Autodesk Fusion 360 part; units mm, degrees
(part 3 of 5)
sketch "belly_pb10" plane through (120.4, 0, 0) normal (1, 0, 0) x (0, 0, -1)
  line L0 (20.5, -27) -> (22.2245, -23.1429)
  line L1 (22.2245, -23.1429) -> (23.6837, -19.2857)
  line L2 (23.6837, -19.2857) -> (24.8776, -15.4286)
  line L3 (24.8776, -15.4286) -> (25.8061, -11.5714)
  line L4 (25.8061, -11.5714) -> (26.4694, -7.7143)
  line L5 (26.4694, -7.7143) -> (26.8673, -3.8571)
  line L6 (26.8673, -3.8571) -> (27, 0)
  line L7 (27, 0) -> (26.8673, 3.8571)
  line L8 (26.8673, 3.8571) -> (26.4694, 7.7143)
  line L9 (26.4694, 7.7143) -> (25.8061, 11.5714)
  line L10 (25.8061, 11.5714) -> (24.8776, 15.4286)
  line L11 (24.8776, 15.4286) -> (23.6837, 19.2857)
  line L12 (23.6837, 19.2857) -> (22.2245, 23.1429)
  line L13 (22.2245, 23.1429) -> (20.5, 27)
  line L14 (20.5, 27) -> (18.5, 27)
  line L15 (18.5, 27) -> (20.2245, 23.1429)
  line L16 (20.2245, 23.1429) -> (21.6837, 19.2857)
  line L17 (21.6837, 19.2857) -> (22.8776, 15.4286)
  line L18 (22.8776, 15.4286) -> (23.8061, 11.5714)
  line L19 (23.8061, 11.5714) -> (24.4694, 7.7143)
  line L20 (24.4694, 7.7143) -> (24.8673, 3.8571)
  line L21 (24.8673, 3.8571) -> (25, 0)
  line L22 (25, 0) -> (24.8673, -3.8571)
  line L23 (24.8673, -3.8571) -> (24.4694, -7.7143)
  line L24 (24.4694, -7.7143) -> (23.8061, -11.5714)
  line L25 (23.8061, -11.5714) -> (22.8776, -15.4286)
  line L26 (22.8776, -15.4286) -> (21.6837, -19.2857)
  line L27 (21.6837, -19.2857) -> (20.2245, -23.1429)
  line L28 (20.2245, -23.1429) -> (18.5, -27)
  line L29 (18.5, -27) -> (20.5, -27)
loft "Loft29" add profiles "belly_pa10", "belly_pb10" section 1 section 2 separate body makes body 29
ref_plane "WorkPlane59" through (119.6, 0, 0) normal (1, 0, 0) x (0, 1, 0)
sketch "belly_pa11" plane through (119.6, 0, 0) normal (1, 0, 0) x (0, 0, -1)
  line L0 (20.5, -27) -> (22.2245, -23.1429)
  line L1 (22.2245, -23.1429) -> (23.6837, -19.2857)
  line L2 (23.6837, -19.2857) -> (24.8776, -15.4286)
  line L3 (24.8776, -15.4286) -> (25.8061, -11.5714)
  line L4 (25.8061, -11.5714) -> (26.4694, -7.7143)
  line L5 (26.4694, -7.7143) -> (26.8673, -3.8571)
  line L6 (26.8673, -3.8571) -> (27, 0)
  line L7 (27, 0) -> (26.8673, 3.8571)
  line L8 (26.8673, 3.8571) -> (26.4694, 7.7143)
  line L9 (26.4694, 7.7143) -> (25.8061, 11.5714)
  line L10 (25.8061, 11.5714) -> (24.8776, 15.4286)
  line L11 (24.8776, 15.4286) -> (23.6837, 19.2857)
  line L12 (23.6837, 19.2857) -> (22.2245, 23.1429)
  line L13 (22.2245, 23.1429) -> (20.5, 27)
  line L14 (20.5, 27) -> (18.5, 27)
  line L15 (18.5, 27) -> (20.2245, 23.1429)
  line L16 (20.2245, 23.1429) -> (21.6837, 19.2857)
  line L17 (21.6837, 19.2857) -> (22.8776, 15.4286)
  line L18 (22.8776, 15.4286) -> (23.8061, 11.5714)
  line L19 (23.8061, 11.5714) -> (24.4694, 7.7143)
  line L20 (24.4694, 7.7143) -> (24.8673, 3.8571)
  line L21 (24.8673, 3.8571) -> (25, 0)
  line L22 (25, 0) -> (24.8673, -3.8571)
  line L23 (24.8673, -3.8571) -> (24.4694, -7.7143)
  line L24 (24.4694, -7.7143) -> (23.8061, -11.5714)
  line L25 (23.8061, -11.5714) -> (22.8776, -15.4286)
  line L26 (22.8776, -15.4286) -> (21.6837, -19.2857)
  line L27 (21.6837, -19.2857) -> (20.2245, -23.1429)
  line L28 (20.2245, -23.1429) -> (18.5, -27)
  line L29 (18.5, -27) -> (20.5, -27)
ref_plane "WorkPlane60" through (124.6857, 0, 0) normal (1, 0, 0) x (0, 1, 0)
sketch "belly_pb11" plane through (124.6857, 0, 0) normal (1, 0, 0) x (0, 0, -1)
  line L0 (18.3003, -24.3221) -> (19.8472, -20.8475)
  line L1 (19.8472, -20.8475) -> (21.1561, -17.3729)
  line L2 (21.1561, -17.3729) -> (22.227, -13.8983)
  line L3 (22.227, -13.8983) -> (23.0599, -10.4238)
  line L4 (23.0599, -10.4238) -> (23.6549, -6.9492)
  line L5 (23.6549, -6.9492) -> (24.0118, -3.4746)
  line L6 (24.0118, -3.4746) -> (24.1308, 0)
  line L7 (24.1308, 0) -> (24.0118, 3.4746)
  line L8 (24.0118, 3.4746) -> (23.6549, 6.9492)
  line L9 (23.6549, 6.9492) -> (23.0599, 10.4238)
  line L10 (23.0599, 10.4238) -> (22.227, 13.8983)
  line L11 (22.227, 13.8983) -> (21.1561, 17.3729)
  line L12 (21.1561, 17.3729) -> (19.8472, 20.8475)
  line L13 (19.8472, 20.8475) -> (18.3003, 24.3221)
  line L14 (18.3003, 24.3221) -> (16.3003, 24.3221)
  line L15 (16.3003, 24.3221) -> (17.8472, 20.8475)
  line L16 (17.8472, 20.8475) -> (19.1561, 17.3729)
  line L17 (19.1561, 17.3729) -> (20.227, 13.8983)
  line L18 (20.227, 13.8983) -> (21.0599, 10.4238)
  line L19 (21.0599, 10.4238) -> (21.6549, 6.9492)
  line L20 (21.6549, 6.9492) -> (22.0118, 3.4746)
  line L21 (22.0118, 3.4746) -> (22.1308, 0)
  line L22 (22.1308, 0) -> (22.0118, -3.4746)
  line L23 (22.0118, -3.4746) -> (21.6549, -6.9492)
  line L24 (21.6549, -6.9492) -> (21.0599, -10.4238)
  line L25 (21.0599, -10.4238) -> (20.227, -13.8983)
  line L26 (20.227, -13.8983) -> (19.1561, -17.3729)
  line L27 (19.1561, -17.3729) -> (17.8472, -20.8475)
  line L28 (17.8472, -20.8475) -> (16.3003, -24.3221)
  line L29 (16.3003, -24.3221) -> (18.3003, -24.3221)
loft "Loft30" add profiles "belly_pa11", "belly_pb11" section 1 section 2 separate body makes body 30
ref_plane "WorkPlane61" through (123.8857, 0, 0) normal (1, 0, 0) x (0, 1, 0)
sketch "belly_pa12" plane through (123.8857, 0, 0) normal (1, 0, 0) x (0, 0, -1)
  line L0 (18.3003, -24.3221) -> (19.8472, -20.8475)
  line L1 (19.8472, -20.8475) -> (21.1561, -17.3729)
  line L2 (21.1561, -17.3729) -> (22.227, -13.8983)
  line L3 (22.227, -13.8983) -> (23.0599, -10.4238)
  line L4 (23.0599, -10.4238) -> (23.6549, -6.9492)
  line L5 (23.6549, -6.9492) -> (24.0118, -3.4746)
  line L6 (24.0118, -3.4746) -> (24.1308, 0)
  line L7 (24.1308, 0) -> (24.0118, 3.4746)
  line L8 (24.0118, 3.4746) -> (23.6549, 6.9492)
  line L9 (23.6549, 6.9492) -> (23.0599, 10.4238)
  line L10 (23.0599, 10.4238) -> (22.227, 13.8983)
  line L11 (22.227, 13.8983) -> (21.1561, 17.3729)
  line L12 (21.1561, 17.3729) -> (19.8472, 20.8475)
  line L13 (19.8472, 20.8475) -> (18.3003, 24.3221)
  line L14 (18.3003, 24.3221) -> (16.3003, 24.3221)
  line L15 (16.3003, 24.3221) -> (17.8472, 20.8475)
  line L16 (17.8472, 20.8475) -> (19.1561, 17.3729)
  line L17 (19.1561, 17.3729) -> (20.227, 13.8983)
  line L18 (20.227, 13.8983) -> (21.0599, 10.4238)
  line L19 (21.0599, 10.4238) -> (21.6549, 6.9492)
  line L20 (21.6549, 6.9492) -> (22.0118, 3.4746)
  line L21 (22.0118, 3.4746) -> (22.1308, 0)
  line L22 (22.1308, 0) -> (22.0118, -3.4746)
  line L23 (22.0118, -3.4746) -> (21.6549, -6.9492)
  line L24 (21.6549, -6.9492) -> (21.0599, -10.4238)
  line L25 (21.0599, -10.4238) -> (20.227, -13.8983)
  line L26 (20.227, -13.8983) -> (19.1561, -17.3729)
  line L27 (19.1561, -17.3729) -> (17.8472, -20.8475)
  line L28 (17.8472, -20.8475) -> (16.3003, -24.3221)
  line L29 (16.3003, -24.3221) -> (18.3003, -24.3221)
ref_plane "WorkPlane62" through (128.9714, 0, 0) normal (1, 0, 0) x (0, 1, 0)
sketch "belly_pb12" plane through (128.9714, 0, 0) normal (1, 0, 0) x (0, 0, -1)
  line L0 (16.535, -22.1731) -> (17.9394, -19.0055)
  line L1 (17.9394, -19.0055) -> (19.1277, -15.8379)
  line L2 (19.1277, -15.8379) -> (20.0999, -12.6703)
  line L3 (20.0999, -12.6703) -> (20.8561, -9.5027)
  line L4 (20.8561, -9.5027) -> (21.3962, -6.3352)
  line L5 (21.3962, -6.3352) -> (21.7203, -3.1676)
  line L6 (21.7203, -3.1676) -> (21.8283, 0)
  line L7 (21.8283, 0) -> (21.7203, 3.1676)
  line L8 (21.7203, 3.1676) -> (21.3962, 6.3352)
  line L9 (21.3962, 6.3352) -> (20.8561, 9.5027)
  line L10 (20.8561, 9.5027) -> (20.0999, 12.6703)
  line L11 (20.0999, 12.6703) -> (19.1277, 15.8379)
  line L12 (19.1277, 15.8379) -> (17.9394, 19.0055)
  line L13 (17.9394, 19.0055) -> (16.535, 22.1731)
  line L14 (16.535, 22.1731) -> (14.535, 22.1731)
  line L15 (14.535, 22.1731) -> (15.9394, 19.0055)
  line L16 (15.9394, 19.0055) -> (17.1277, 15.8379)
  line L17 (17.1277, 15.8379) -> (18.0999, 12.6703)
  line L18 (18.0999, 12.6703) -> (18.8561, 9.5027)
  line L19 (18.8561, 9.5027) -> (19.3962, 6.3352)
  line L20 (19.3962, 6.3352) -> (19.7203, 3.1676)
  line L21 (19.7203, 3.1676) -> (19.8283, 0)
  line L22 (19.8283, 0) -> (19.7203, -3.1676)
  line L23 (19.7203, -3.1676) -> (19.3962, -6.3352)
  line L24 (19.3962, -6.3352) -> (18.8561, -9.5027)
  line L25 (18.8561, -9.5027) -> (18.0999, -12.6703)
  line L26 (18.0999, -12.6703) -> (17.1277, -15.8379)
  line L27 (17.1277, -15.8379) -> (15.9394, -19.0055)
  line L28 (15.9394, -19.0055) -> (14.535, -22.1731)
  line L29 (14.535, -22.1731) -> (16.535, -22.1731)
loft "Loft31" add profiles "belly_pa12", "belly_pb12" section 1 section 2 separate body makes body 31
ref_plane "WorkPlane63" through (128.1714, 0, 0) normal (1, 0, 0) x (0, 1, 0)
sketch "belly_pa13" plane through (128.1714, 0, 0) normal (1, 0, 0) x (0, 0, -1)
  line L0 (16.535, -22.1731) -> (17.9394, -19.0055)
  line L1 (17.9394, -19.0055) -> (19.1277, -15.8379)
  line L2 (19.1277, -15.8379) -> (20.0999, -12.6703)
  line L3 (20.0999, -12.6703) -> (20.8561, -9.5027)
  line L4 (20.8561, -9.5027) -> (21.3962, -6.3352)
  line L5 (21.3962, -6.3352) -> (21.7203, -3.1676)
  line L6 (21.7203, -3.1676) -> (21.8283, 0)
  line L7 (21.8283, 0) -> (21.7203, 3.1676)
  line L8 (21.7203, 3.1676) -> (21.3962, 6.3352)
  line L9 (21.3962, 6.3352) -> (20.8561, 9.5027)
  line L10 (20.8561, 9.5027) -> (20.0999, 12.6703)
  line L11 (20.0999, 12.6703) -> (19.1277, 15.8379)
  line L12 (19.1277, 15.8379) -> (17.9394, 19.0055)
  line L13 (17.9394, 19.0055) -> (16.535, 22.1731)
  line L14 (16.535, 22.1731) -> (14.535, 22.1731)
  line L15 (14.535, 22.1731) -> (15.9394, 19.0055)
  line L16 (15.9394, 19.0055) -> (17.1277, 15.8379)
  line L17 (17.1277, 15.8379) -> (18.0999, 12.6703)
  line L18 (18.0999, 12.6703) -> (18.8561, 9.5027)
  line L19 (18.8561, 9.5027) -> (19.3962, 6.3352)
  line L20 (19.3962, 6.3352) -> (19.7203, 3.1676)
  line L21 (19.7203, 3.1676) -> (19.8283, 0)
  line L22 (19.8283, 0) -> (19.7203, -3.1676)
  line L23 (19.7203, -3.1676) -> (19.3962, -6.3352)
  line L24 (19.3962, -6.3352) -> (18.8561, -9.5027)
  line L25 (18.8561, -9.5027) -> (18.0999, -12.6703)
  line L26 (18.0999, -12.6703) -> (17.1277, -15.8379)
  line L27 (17.1277, -15.8379) -> (15.9394, -19.0055)
  line L28 (15.9394, -19.0055) -> (14.535, -22.1731)
  line L29 (14.535, -22.1731) -> (16.535, -22.1731)
ref_plane "WorkPlane64" through (133.2571, 0, 0) normal (1, 0, 0) x (0, 1, 0)
sketch "belly_pb13" plane through (133.2571, 0, 0) normal (1, 0, 0) x (0, 0, -1)
  line L0 (14.9035, -20.1869) -> (16.1761, -17.303)
  line L1 (16.1761, -17.303) -> (17.2529, -14.4192)
  line L2 (17.2529, -14.4192) -> (18.1339, -11.5353)
  line L3 (18.1339, -11.5353) -> (18.8192, -8.6515)
  line L4 (18.8192, -8.6515) -> (19.3086, -5.7677)
  line L5 (19.3086, -5.7677) -> (19.6023, -2.8838)
  line L6 (19.6023, -2.8838) -> (19.7002, 0)
  line L7 (19.7002, 0) -> (19.6023, 2.8838)
  line L8 (19.6023, 2.8838) -> (19.3086, 5.7677)
  line L9 (19.3086, 5.7677) -> (18.8192, 8.6515)
  line L10 (18.8192, 8.6515) -> (18.1339, 11.5353)
  line L11 (18.1339, 11.5353) -> (17.2529, 14.4192)
  line L12 (17.2529, 14.4192) -> (16.1761, 17.303)
  line L13 (16.1761, 17.303) -> (14.9035, 20.1869)
  line L14 (14.9035, 20.1869) -> (12.9035, 20.1869)
  line L15 (12.9035, 20.1869) -> (14.1761, 17.303)
  line L16 (14.1761, 17.303) -> (15.2529, 14.4192)
  line L17 (15.2529, 14.4192) -> (16.1339, 11.5353)
  line L18 (16.1339, 11.5353) -> (16.8192, 8.6515)
  line L19 (16.8192, 8.6515) -> (17.3086, 5.7677)
  line L20 (17.3086, 5.7677) -> (17.6023, 2.8838)
  line L21 (17.6023, 2.8838) -> (17.7002, 0)
  line L22 (17.7002, 0) -> (17.6023, -2.8838)
  line L23 (17.6023, -2.8838) -> (17.3086, -5.7677)
  line L24 (17.3086, -5.7677) -> (16.8192, -8.6515)
  line L25 (16.8192, -8.6515) -> (16.1339, -11.5353)
  line L26 (16.1339, -11.5353) -> (15.2529, -14.4192)
  line L27 (15.2529, -14.4192) -> (14.1761, -17.303)
  line L28 (14.1761, -17.303) -> (12.9035, -20.1869)
  line L29 (12.9035, -20.1869) -> (14.9035, -20.1869)
loft "Loft32" add profiles "belly_pa13", "belly_pb13" section 1 section 2 separate body makes body 32
ref_plane "WorkPlane65" through (132.4571, 0, 0) normal (1, 0, 0) x (0, 1, 0)
sketch "belly_pa14" plane through (132.4571, 0, 0) normal (1, 0, 0) x (0, 0, -1)
  line L0 (14.9035, -20.1869) -> (16.1761, -17.303)
  line L1 (16.1761, -17.303) -> (17.2529, -14.4192)
  line L2 (17.2529, -14.4192) -> (18.1339, -11.5353)
  line L3 (18.1339, -11.5353) -> (18.8192, -8.6515)
  line L4 (18.8192, -8.6515) -> (19.3086, -5.7677)
  line L5 (19.3086, -5.7677) -> (19.6023, -2.8838)
  line L6 (19.6023, -2.8838) -> (19.7002, 0)
  line L7 (19.7002, 0) -> (19.6023, 2.8838)
  line L8 (19.6023, 2.8838) -> (19.3086, 5.7677)
  line L9 (19.3086, 5.7677) -> (18.8192, 8.6515)
  line L10 (18.8192, 8.6515) -> (18.1339, 11.5353)
  line L11 (18.1339, 11.5353) -> (17.2529, 14.4192)
  line L12 (17.2529, 14.4192) -> (16.1761, 17.303)
  line L13 (16.1761, 17.303) -> (14.9035, 20.1869)
  line L14 (14.9035, 20.1869) -> (12.9035, 20.1869)
  line L15 (12.9035, 20.1869) -> (14.1761, 17.303)
  line L16 (14.1761, 17.303) -> (15.2529, 14.4192)
  line L17 (15.2529, 14.4192) -> (16.1339, 11.5353)
  line L18 (16.1339, 11.5353) -> (16.8192, 8.6515)
  line L19 (16.8192, 8.6515) -> (17.3086, 5.7677)
  line L20 (17.3086, 5.7677) -> (17.6023, 2.8838)
  line L21 (17.6023, 2.8838) -> (17.7002, 0)
  line L22 (17.7002, 0) -> (17.6023, -2.8838)
  line L23 (17.6023, -2.8838) -> (17.3086, -5.7677)
  line L24 (17.3086, -5.7677) -> (16.8192, -8.6515)
  line L25 (16.8192, -8.6515) -> (16.1339, -11.5353)
  line L26 (16.1339, -11.5353) -> (15.2529, -14.4192)
  line L27 (15.2529, -14.4192) -> (14.1761, -17.303)
  line L28 (14.1761, -17.303) -> (12.9035, -20.1869)
  line L29 (12.9035, -20.1869) -> (14.9035, -20.1869)
ref_plane "WorkPlane66" through (137.5429, 0, 0) normal (1, 0, 0) x (0, 1, 0)
sketch "belly_pb14" plane through (137.5429, 0, 0) normal (1, 0, 0) x (0, 0, -1)
  line L0 (13.3531, -18.2995) -> (14.5006, -15.6853)
  line L1 (14.5006, -15.6853) -> (15.4714, -13.0711)
  line L2 (15.4714, -13.0711) -> (16.2658, -10.4568)
  line L3 (16.2658, -10.4568) -> (16.8836, -7.8426)
  line L4 (16.8836, -7.8426) -> (17.325, -5.2284)
  line L5 (17.325, -5.2284) -> (17.5897, -2.6142)
  line L6 (17.5897, -2.6142) -> (17.678, 0)
  line L7 (17.678, 0) -> (17.5897, 2.6142)
  line L8 (17.5897, 2.6142) -> (17.325, 5.2284)
  line L9 (17.325, 5.2284) -> (16.8836, 7.8426)
  line L10 (16.8836, 7.8426) -> (16.2658, 10.4568)
  line L11 (16.2658, 10.4568) -> (15.4714, 13.0711)
  line L12 (15.4714, 13.0711) -> (14.5006, 15.6853)
  line L13 (14.5006, 15.6853) -> (13.3531, 18.2995)
  line L14 (13.3531, 18.2995) -> (11.3531, 18.2995)
  line L15 (11.3531, 18.2995) -> (12.5006, 15.6853)
  line L16 (12.5006, 15.6853) -> (13.4714, 13.0711)
  line L17 (13.4714, 13.0711) -> (14.2658, 10.4568)
  line L18 (14.2658, 10.4568) -> (14.8836, 7.8426)
  line L19 (14.8836, 7.8426) -> (15.325, 5.2284)
  line L20 (15.325, 5.2284) -> (15.5897, 2.6142)
  line L21 (15.5897, 2.6142) -> (15.678, 0)
  line L22 (15.678, 0) -> (15.5897, -2.6142)
  line L23 (15.5897, -2.6142) -> (15.325, -5.2284)
  line L24 (15.325, -5.2284) -> (14.8836, -7.8426)
  line L25 (14.8836, -7.8426) -> (14.2658, -10.4568)
  line L26 (14.2658, -10.4568) -> (13.4714, -13.0711)
  line L27 (13.4714, -13.0711) -> (12.5006, -15.6853)
  line L28 (12.5006, -15.6853) -> (11.3531, -18.2995)
  line L29 (11.3531, -18.2995) -> (13.3531, -18.2995)
loft "Loft33" add profiles "belly_pa14", "belly_pb14" section 1 section 2 separate body makes body 33
ref_plane "WorkPlane67" through (136.7429, 0, 0) normal (1, 0, 0) x (0, 1, 0)
sketch "belly_pa15" plane through (136.7429, 0, 0) normal (1, 0, 0) x (0, 0, -1)
  line L0 (13.3531, -18.2995) -> (14.5006, -15.6853)
  line L1 (14.5006, -15.6853) -> (15.4714, -13.0711)
  line L2 (15.4714, -13.0711) -> (16.2658, -10.4568)
  line L3 (16.2658, -10.4568) -> (16.8836, -7.8426)
  line L4 (16.8836, -7.8426) -> (17.325, -5.2284)
  line L5 (17.325, -5.2284) -> (17.5897, -2.6142)
  line L6 (17.5897, -2.6142) -> (17.678, 0)
  line L7 (17.678, 0) -> (17.5897, 2.6142)
  line L8 (17.5897, 2.6142) -> (17.325, 5.2284)
  line L9 (17.325, 5.2284) -> (16.8836, 7.8426)
  line L10 (16.8836, 7.8426) -> (16.2658, 10.4568)
  line L11 (16.2658, 10.4568) -> (15.4714, 13.0711)
  line L12 (15.4714, 13.0711) -> (14.5006, 15.6853)
  line L13 (14.5006, 15.6853) -> (13.3531, 18.2995)
  line L14 (13.3531, 18.2995) -> (11.3531, 18.2995)
  line L15 (11.3531, 18.2995) -> (12.5006, 15.6853)
  line L16 (12.5006, 15.6853) -> (13.4714, 13.0711)
  line L17 (13.4714, 13.0711) -> (14.2658, 10.4568)
  line L18 (14.2658, 10.4568) -> (14.8836, 7.8426)
  line L19 (14.8836, 7.8426) -> (15.325, 5.2284)
  line L20 (15.325, 5.2284) -> (15.5897, 2.6142)
  line L21 (15.5897, 2.6142) -> (15.678, 0)
  line L22 (15.678, 0) -> (15.5897, -2.6142)
  line L23 (15.5897, -2.6142) -> (15.325, -5.2284)
  line L24 (15.325, -5.2284) -> (14.8836, -7.8426)
  line L25 (14.8836, -7.8426) -> (14.2658, -10.4568)
  line L26 (14.2658, -10.4568) -> (13.4714, -13.0711)
  line L27 (13.4714, -13.0711) -> (12.5006, -15.6853)
  line L28 (12.5006, -15.6853) -> (11.3531, -18.2995)
  line L29 (11.3531, -18.2995) -> (13.3531, -18.2995)
ref_plane "WorkPlane68" through (141.8286, 0, 0) normal (1, 0, 0) x (0, 1, 0)
sketch "belly_pb15" plane through (141.8286, 0, 0) normal (1, 0, 0) x (0, 0, -1)
  line L0 (11.8605, -16.4823) -> (12.8874, -14.1277)
  line L1 (12.8874, -14.1277) -> (13.7563, -11.7731)
  line L2 (13.7563, -11.7731) -> (14.4672, -9.4185)
  line L3 (14.4672, -9.4185) -> (15.0202, -7.0639)
  line L4 (15.0202, -7.0639) -> (15.4151, -4.7092)
  line L5 (15.4151, -4.7092) -> (15.6521, -2.3546)
  line L6 (15.6521, -2.3546) -> (15.7311, 0)
  line L7 (15.7311, 0) -> (15.6521, 2.3546)
  line L8 (15.6521, 2.3546) -> (15.4151, 4.7092)
  line L9 (15.4151, 4.7092) -> (15.0202, 7.0639)
  line L10 (15.0202, 7.0639) -> (14.4672, 9.4185)
  line L11 (14.4672, 9.4185) -> (13.7563, 11.7731)
  line L12 (13.7563, 11.7731) -> (12.8874, 14.1277)
  line L13 (12.8874, 14.1277) -> (11.8605, 16.4823)
  line L14 (11.8605, 16.4823) -> (9.8605, 16.4823)
  line L15 (9.8605, 16.4823) -> (10.8874, 14.1277)
  line L16 (10.8874, 14.1277) -> (11.7563, 11.7731)
  line L17 (11.7563, 11.7731) -> (12.4672, 9.4185)
  line L18 (12.4672, 9.4185) -> (13.0202, 7.0639)
  line L19 (13.0202, 7.0639) -> (13.4151, 4.7092)
  line L20 (13.4151, 4.7092) -> (13.6521, 2.3546)
  line L21 (13.6521, 2.3546) -> (13.7311, 0)
  line L22 (13.7311, 0) -> (13.6521, -2.3546)
  line L23 (13.6521, -2.3546) -> (13.4151, -4.7092)
  line L24 (13.4151, -4.7092) -> (13.0202, -7.0639)
  line L25 (13.0202, -7.0639) -> (12.4672, -9.4185)
  line L26 (12.4672, -9.4185) -> (11.7563, -11.7731)
  line L27 (11.7563, -11.7731) -> (10.8874, -14.1277)
  line L28 (10.8874, -14.1277) -> (9.8605, -16.4823)
  line L29 (9.8605, -16.4823) -> (11.8605, -16.4823)
loft "Loft34" add profiles "belly_pa15", "belly_pb15" section 1 section 2 separate body makes body 34
ref_plane "WorkPlane69" through (141.0286, 0, 0) normal (1, 0, 0) x (0, 1, 0)
sketch "belly_pa16" plane through (141.0286, 0, 0) normal (1, 0, 0) x (0, 0, -1)
  line L0 (11.8605, -16.4823) -> (12.8874, -14.1277)
  line L1 (12.8874, -14.1277) -> (13.7563, -11.7731)
  line L2 (13.7563, -11.7731) -> (14.4672, -9.4185)
  line L3 (14.4672, -9.4185) -> (15.0202, -7.0639)
  line L4 (15.0202, -7.0639) -> (15.4151, -4.7092)
  line L5 (15.4151, -4.7092) -> (15.6521, -2.3546)
  line L6 (15.6521, -2.3546) -> (15.7311, 0)
  line L7 (15.7311, 0) -> (15.6521, 2.3546)
  line L8 (15.6521, 2.3546) -> (15.4151, 4.7092)
  line L9 (15.4151, 4.7092) -> (15.0202, 7.0639)
  line L10 (15.0202, 7.0639) -> (14.4672, 9.4185)
  line L11 (14.4672, 9.4185) -> (13.7563, 11.7731)
  line L12 (13.7563, 11.7731) -> (12.8874, 14.1277)
  line L13 (12.8874, 14.1277) -> (11.8605, 16.4823)
  line L14 (11.8605, 16.4823) -> (9.8605, 16.4823)
  line L15 (9.8605, 16.4823) -> (10.8874, 14.1277)
  line L16 (10.8874, 14.1277) -> (11.7563, 11.7731)
  line L17 (11.7563, 11.7731) -> (12.4672, 9.4185)
  line L18 (12.4672, 9.4185) -> (13.0202, 7.0639)
  line L19 (13.0202, 7.0639) -> (13.4151, 4.7092)
  line L20 (13.4151, 4.7092) -> (13.6521, 2.3546)
  line L21 (13.6521, 2.3546) -> (13.7311, 0)
  line L22 (13.7311, 0) -> (13.6521, -2.3546)
  line L23 (13.6521, -2.3546) -> (13.4151, -4.7092)
  line L24 (13.4151, -4.7092) -> (13.0202, -7.0639)
  line L25 (13.0202, -7.0639) -> (12.4672, -9.4185)
  line L26 (12.4672, -9.4185) -> (11.7563, -11.7731)
  line L27 (11.7563, -11.7731) -> (10.8874, -14.1277)
  line L28 (10.8874, -14.1277) -> (9.8605, -16.4823)
  line L29 (9.8605, -16.4823) -> (11.8605, -16.4823)
ref_plane "WorkPlane70" through (146.1143, 0, 0) normal (1, 0, 0) x (0, 1, 0)
sketch "belly_pb16" plane through (146.1143, 0, 0) normal (1, 0, 0) x (0, 0, -1)
  line L0 (10.4123, -14.7193) -> (11.3222, -12.6165)
  line L1 (11.3222, -12.6165) -> (12.0922, -10.5138)
  line L2 (12.0922, -10.5138) -> (12.7222, -8.411)
  line L3 (12.7222, -8.411) -> (13.2121, -6.3083)
  line L4 (13.2121, -6.3083) -> (13.5621, -4.2055)
  line L5 (13.5621, -4.2055) -> (13.7721, -2.1028)
  line L6 (13.7721, -2.1028) -> (13.8421, 0)
  line L7 (13.8421, 0) -> (13.7721, 2.1028)
  line L8 (13.7721, 2.1028) -> (13.5621, 4.2055)
  line L9 (13.5621, 4.2055) -> (13.2121, 6.3083)
  line L10 (13.2121, 6.3083) -> (12.7222, 8.411)
  line L11 (12.7222, 8.411) -> (12.0922, 10.5138)
  line L12 (12.0922, 10.5138) -> (11.3222, 12.6165)
  line L13 (11.3222, 12.6165) -> (10.4123, 14.7193)
  line L14 (10.4123, 14.7193) -> (8.4123, 14.7193)
  line L15 (8.4123, 14.7193) -> (9.3222, 12.6165)
  line L16 (9.3222, 12.6165) -> (10.0922, 10.5138)
  line L17 (10.0922, 10.5138) -> (10.7222, 8.411)
  line L18 (10.7222, 8.411) -> (11.2121, 6.3083)
  line L19 (11.2121, 6.3083) -> (11.5621, 4.2055)
  line L20 (11.5621, 4.2055) -> (11.7721, 2.1028)
  line L21 (11.7721, 2.1028) -> (11.8421, 0)
  line L22 (11.8421, 0) -> (11.7721, -2.1028)
  line L23 (11.7721, -2.1028) -> (11.5621, -4.2055)
  line L24 (11.5621, -4.2055) -> (11.2121, -6.3083)
  line L25 (11.2121, -6.3083) -> (10.7222, -8.411)
  line L26 (10.7222, -8.411) -> (10.0922, -10.5138)
  line L27 (10.0922, -10.5138) -> (9.3222, -12.6165)
  line L28 (9.3222, -12.6165) -> (8.4123, -14.7193)
  line L29 (8.4123, -14.7193) -> (10.4123, -14.7193)
loft "Loft35" add profiles "belly_pa16", "belly_pb16" section 1 section 2 separate body makes body 35
ref_plane "WorkPlane71" through (145.3143, 0, 0) normal (1, 0, 0) x (0, 1, 0)
sketch "belly_pa17" plane through (145.3143, 0, 0) normal (1, 0, 0) x (0, 0, -1)
  line L0 (10.4123, -14.7193) -> (11.3222, -12.6165)
  line L1 (11.3222, -12.6165) -> (12.0922, -10.5138)
  line L2 (12.0922, -10.5138) -> (12.7222, -8.411)
  line L3 (12.7222, -8.411) -> (13.2121, -6.3083)
  line L4 (13.2121, -6.3083) -> (13.5621, -4.2055)
  line L5 (13.5621, -4.2055) -> (13.7721, -2.1028)
  line L6 (13.7721, -2.1028) -> (13.8421, 0)
  line L7 (13.8421, 0) -> (13.7721, 2.1028)
  line L8 (13.7721, 2.1028) -> (13.5621, 4.2055)
  line L9 (13.5621, 4.2055) -> (13.2121, 6.3083)
  line L10 (13.2121, 6.3083) -> (12.7222, 8.411)
  line L11 (12.7222, 8.411) -> (12.0922, 10.5138)
  line L12 (12.0922, 10.5138) -> (11.3222, 12.6165)
  line L13 (11.3222, 12.6165) -> (10.4123, 14.7193)
  line L14 (10.4123, 14.7193) -> (8.4123, 14.7193)
  line L15 (8.4123, 14.7193) -> (9.3222, 12.6165)
  line L16 (9.3222, 12.6165) -> (10.0922, 10.5138)
  line L17 (10.0922, 10.5138) -> (10.7222, 8.411)
  line L18 (10.7222, 8.411) -> (11.2121, 6.3083)
  line L19 (11.2121, 6.3083) -> (11.5621, 4.2055)
  line L20 (11.5621, 4.2055) -> (11.7721, 2.1028)
  line L21 (11.7721, 2.1028) -> (11.8421, 0)
  line L22 (11.8421, 0) -> (11.7721, -2.1028)
  line L23 (11.7721, -2.1028) -> (11.5621, -4.2055)
  line L24 (11.5621, -4.2055) -> (11.2121, -6.3083)
  line L25 (11.2121, -6.3083) -> (10.7222, -8.411)
  line L26 (10.7222, -8.411) -> (10.0922, -10.5138)
  line L27 (10.0922, -10.5138) -> (9.3222, -12.6165)
  line L28 (9.3222, -12.6165) -> (8.4123, -14.7193)
  line L29 (8.4123, -14.7193) -> (10.4123, -14.7193)
ref_plane "WorkPlane72" through (150, 0, 0) normal (1, 0, 0) x (0, 1, 0)
sketch "belly_pb17" plane through (150, 0, 0) normal (1, 0, 0) x (0, 0, -1)
  line L0 (9, -13) -> (9.7959, -11.1429)
  line L1 (9.7959, -11.1429) -> (10.4694, -9.2857)
  line L2 (10.4694, -9.2857) -> (11.0204, -7.4286)
  line L3 (11.0204, -7.4286) -> (11.449, -5.5714)
  line L4 (11.449, -5.5714) -> (11.7551, -3.7143)
  line L5 (11.7551, -3.7143) -> (11.9388, -1.8571)
  line L6 (11.9388, -1.8571) -> (12, 0)
  line L7 (12, 0) -> (11.9388, 1.8571)
  line L8 (11.9388, 1.8571) -> (11.7551, 3.7143)
  line L9 (11.7551, 3.7143) -> (11.449, 5.5714)
  line L10 (11.449, 5.5714) -> (11.0204, 7.4286)
  line L11 (11.0204, 7.4286) -> (10.4694, 9.2857)
  line L12 (10.4694, 9.2857) -> (9.7959, 11.1429)
  line L13 (9.7959, 11.1429) -> (9, 13)
  line L14 (9, 13) -> (7, 13)
  line L15 (7, 13) -> (7.7959, 11.1429)
  line L16 (7.7959, 11.1429) -> (8.4694, 9.2857)
  line L17 (8.4694, 9.2857) -> (9.0204, 7.4286)
  line L18 (9.0204, 7.4286) -> (9.449, 5.5714)
  line L19 (9.449, 5.5714) -> (9.7551, 3.7143)
  line L20 (9.7551, 3.7143) -> (9.9388, 1.8571)
  line L21 (9.9388, 1.8571) -> (10, 0)
  line L22 (10, 0) -> (9.9388, -1.8571)
  line L23 (9.9388, -1.8571) -> (9.7551, -3.7143)
  line L24 (9.7551, -3.7143) -> (9.449, -5.5714)
  line L25 (9.449, -5.5714) -> (9.0204, -7.4286)
  line L26 (9.0204, -7.4286) -> (8.4694, -9.2857)
  line L27 (8.4694, -9.2857) -> (7.7959, -11.1429)
  line L28 (7.7959, -11.1429) -> (7, -13)
  line L29 (7, -13) -> (9, -13)
loft "Loft36" add profiles "belly_pa17", "belly_pb17" section 1 section 2 separate body makes body 36
ref_plane "WorkPlane73" through (-24, 0, 0) normal (1, 0, 0) x (0, 1, 0)
sketch "cheekR_pa00" plane through (-24, 0, 0) normal (1, 0, 0) x (0, 0, -1)
  line L0 (22.5, 33) -> (18, 33)
  line L1 (18, 33) -> (13.5, 33)
  line L2 (13.5, 33) -> (9, 33)
  line L3 (9, 33) -> (4.5, 33)
  line L4 (4.5, 33) -> (0, 33)
  line L5 (0, 33) -> (-4.5, 33)
  line L6 (-4.5, 33) -> (-9, 33)
  line L7 (-9, 33) -> (-13.5, 33)
  line L8 (-13.5, 33) -> (-18, 33)
  line L9 (-18, 33) -> (-22.5, 33)
  line L10 (-22.5, 33) -> (-22.5, 31)
  line L11 (-22.5, 31) -> (-18, 31)
  line L12 (-18, 31) -> (-13.5, 31)
  line L13 (-13.5, 31) -> (-9, 31)
  line L14 (-9, 31) -> (-4.5, 31)
  line L15 (-4.5, 31) -> (0, 31)
  line L16 (0, 31) -> (4.5, 31)
  line L17 (4.5, 31) -> (9, 31)
  line L18 (9, 31) -> (13.5, 31)
  line L19 (13.5, 31) -> (18, 31)
  line L20 (18, 31) -> (22.5, 31)
  line L21 (22.5, 31) -> (22.5, 33)
ref_plane "WorkPlane74" through (-20.1714, 0, 0) normal (1, 0, 0) x (0, 1, 0)
sketch "cheekR_pb00" plane through (-20.1714, 0, 0) normal (1, 0, 0) x (0, 0, -1)
  line L0 (22.3997, 32.8496) -> (17.9198, 32.8496)
  line L1 (17.9198, 32.8496) -> (13.4398, 32.8496)
  line L2 (13.4398, 32.8496) -> (8.9599, 32.8496)
  line L3 (8.9599, 32.8496) -> (4.4799, 32.8496)
  line L4 (4.4799, 32.8496) -> (0, 32.8496)
  line L5 (0, 32.8496) -> (-4.4799, 32.8496)
  line L6 (-4.4799, 32.8496) -> (-8.9599, 32.8496)
  line L7 (-8.9599, 32.8496) -> (-13.4398, 32.8496)
  line L8 (-13.4398, 32.8496) -> (-17.9198, 32.8496)
  line L9 (-17.9198, 32.8496) -> (-22.3997, 32.8496)
  line L10 (-22.3997, 32.8496) -> (-22.3997, 30.8496)
  line L11 (-22.3997, 30.8496) -> (-17.9198, 30.8496)
  line L12 (-17.9198, 30.8496) -> (-13.4398, 30.8496)
  line L13 (-13.4398, 30.8496) -> (-8.9599, 30.8496)
  line L14 (-8.9599, 30.8496) -> (-4.4799, 30.8496)
  line L15 (-4.4799, 30.8496) -> (0, 30.8496)
  line L16 (0, 30.8496) -> (4.4799, 30.8496)
  line L17 (4.4799, 30.8496) -> (8.9599, 30.8496)
  line L18 (8.9599, 30.8496) -> (13.4398, 30.8496)
  line L19 (13.4398, 30.8496) -> (17.9198, 30.8496)
  line L20 (17.9198, 30.8496) -> (22.3997, 30.8496)
  line L21 (22.3997, 30.8496) -> (22.3997, 32.8496)
loft "Loft37" add profiles "cheekR_pa00", "cheekR_pb00" section 1 section 2 separate body makes body 37
ref_plane "WorkPlane75" through (-20.9714, 0, 0) normal (1, 0, 0) x (0, 1, 0)
sketch "cheekR_pa01" plane through (-20.9714, 0, 0) normal (1, 0, 0) x (0, 0, -1)
  line L0 (22.3997, 32.8496) -> (17.9198, 32.8496)
  line L1 (17.9198, 32.8496) -> (13.4398, 32.8496)
  line L2 (13.4398, 32.8496) -> (8.9599, 32.8496)
  line L3 (8.9599, 32.8496) -> (4.4799, 32.8496)
  line L4 (4.4799, 32.8496) -> (0, 32.8496)
  line L5 (0, 32.8496) -> (-4.4799, 32.8496)
  line L6 (-4.4799, 32.8496) -> (-8.9599, 32.8496)
  line L7 (-8.9599, 32.8496) -> (-13.4398, 32.8496)
  line L8 (-13.4398, 32.8496) -> (-17.9198, 32.8496)
  line L9 (-17.9198, 32.8496) -> (-22.3997, 32.8496)
  line L10 (-22.3997, 32.8496) -> (-22.3997, 30.8496)
  line L11 (-22.3997, 30.8496) -> (-17.9198, 30.8496)
  line L12 (-17.9198, 30.8496) -> (-13.4398, 30.8496)
  line L13 (-13.4398, 30.8496) -> (-8.9599, 30.8496)
  line L14 (-8.9599, 30.8496) -> (-4.4799, 30.8496)
  line L15 (-4.4799, 30.8496) -> (0, 30.8496)
  line L16 (0, 30.8496) -> (4.4799, 30.8496)
  line L17 (4.4799, 30.8496) -> (8.9599, 30.8496)
  line L18 (8.9599, 30.8496) -> (13.4398, 30.8496)
  line L19 (13.4398, 30.8496) -> (17.9198, 30.8496)
  line L20 (17.9198, 30.8496) -> (22.3997, 30.8496)
  line L21 (22.3997, 30.8496) -> (22.3997, 32.8496)
ref_plane "WorkPlane76" through (-16.7429, 0, 0) normal (1, 0, 0) x (0, 1, 0)
sketch "cheekR_pb01" plane through (-16.7429, 0, 0) normal (1, 0, 0) x (0, 0, -1)
  line L0 (22.1039, 32.4058) -> (17.6831, 32.4058)
  line L1 (17.6831, 32.4058) -> (13.2623, 32.4058)
  line L2 (13.2623, 32.4058) -> (8.8416, 32.4058)
  line L3 (8.8416, 32.4058) -> (4.4208, 32.4058)
  line L4 (4.4208, 32.4058) -> (0, 32.4058)
  line L5 (0, 32.4058) -> (-4.4208, 32.4058)
  line L6 (-4.4208, 32.4058) -> (-8.8416, 32.4058)
  line L7 (-8.8416, 32.4058) -> (-13.2623, 32.4058)
  line L8 (-13.2623, 32.4058) -> (-17.6831, 32.4058)
  line L9 (-17.6831, 32.4058) -> (-22.1039, 32.4058)
  line L10 (-22.1039, 32.4058) -> (-22.1039, 30.4058)
  line L11 (-22.1039, 30.4058) -> (-17.6831, 30.4058)
  line L12 (-17.6831, 30.4058) -> (-13.2623, 30.4058)
  line L13 (-13.2623, 30.4058) -> (-8.8416, 30.4058)
  line L14 (-8.8416, 30.4058) -> (-4.4208, 30.4058)
  line L15 (-4.4208, 30.4058) -> (0, 30.4058)
  line L16 (0, 30.4058) -> (4.4208, 30.4058)
  line L17 (4.4208, 30.4058) -> (8.8416, 30.4058)
  line L18 (8.8416, 30.4058) -> (13.2623, 30.4058)
  line L19 (13.2623, 30.4058) -> (17.6831, 30.4058)
  line L20 (17.6831, 30.4058) -> (22.1039, 30.4058)
  line L21 (22.1039, 30.4058) -> (22.1039, 32.4058)
loft "Loft38" add profiles "cheekR_pa01", "cheekR_pb01" section 1 section 2 separate body makes body 38
ref_plane "WorkPlane77" through (-17.5429, 0, 0) normal (1, 0, 0) x (0, 1, 0)
sketch "cheekR_pa02" plane through (-17.5429, 0, 0) normal (1, 0, 0) x (0, 0, -1)
  line L0 (22.1039, 32.4058) -> (17.6831, 32.4058)
  line L1 (17.6831, 32.4058) -> (13.2623, 32.4058)
  line L2 (13.2623, 32.4058) -> (8.8416, 32.4058)
  line L3 (8.8416, 32.4058) -> (4.4208, 32.4058)
  line L4 (4.4208, 32.4058) -> (0, 32.4058)
  line L5 (0, 32.4058) -> (-4.4208, 32.4058)
  line L6 (-4.4208, 32.4058) -> (-8.8416, 32.4058)
  line L7 (-8.8416, 32.4058) -> (-13.2623, 32.4058)
  line L8 (-13.2623, 32.4058) -> (-17.6831, 32.4058)
  line L9 (-17.6831, 32.4058) -> (-22.1039, 32.4058)
  line L10 (-22.1039, 32.4058) -> (-22.1039, 30.4058)
  line L11 (-22.1039, 30.4058) -> (-17.6831, 30.4058)
  line L12 (-17.6831, 30.4058) -> (-13.2623, 30.4058)
  line L13 (-13.2623, 30.4058) -> (-8.8416, 30.4058)
  line L14 (-8.8416, 30.4058) -> (-4.4208, 30.4058)
  line L15 (-4.4208, 30.4058) -> (0, 30.4058)
  line L16 (0, 30.4058) -> (4.4208, 30.4058)
  line L17 (4.4208, 30.4058) -> (8.8416, 30.4058)
  line L18 (8.8416, 30.4058) -> (13.2623, 30.4058)
  line L19 (13.2623, 30.4058) -> (17.6831, 30.4058)
  line L20 (17.6831, 30.4058) -> (22.1039, 30.4058)
  line L21 (22.1039, 30.4058) -> (22.1039, 32.4058)
ref_plane "WorkPlane78" through (-13.3143, 0, 0) normal (1, 0, 0) x (0, 1, 0)
sketch "cheekR_pb02" plane through (-13.3143, 0, 0) normal (1, 0, 0) x (0, 0, -1)
  line L0 (21.6273, 31.691) -> (17.3019, 31.691)
  line L1 (17.3019, 31.691) -> (12.9764, 31.691)
  line L2 (12.9764, 31.691) -> (8.6509, 31.691)
  line L3 (8.6509, 31.691) -> (4.3255, 31.691)
  line L4 (4.3255, 31.691) -> (0, 31.691)
  line L5 (0, 31.691) -> (-4.3255, 31.691)
  line L6 (-4.3255, 31.691) -> (-8.6509, 31.691)
  line L7 (-8.6509, 31.691) -> (-12.9764, 31.691)
  line L8 (-12.9764, 31.691) -> (-17.3019, 31.691)
  line L9 (-17.3019, 31.691) -> (-21.6273, 31.691)
  line L10 (-21.6273, 31.691) -> (-21.6273, 29.691)
  line L11 (-21.6273, 29.691) -> (-17.3019, 29.691)
  line L12 (-17.3019, 29.691) -> (-12.9764, 29.691)
  line L13 (-12.9764, 29.691) -> (-8.6509, 29.691)
  line L14 (-8.6509, 29.691) -> (-4.3255, 29.691)
  line L15 (-4.3255, 29.691) -> (0, 29.691)
  line L16 (0, 29.691) -> (4.3255, 29.691)
  line L17 (4.3255, 29.691) -> (8.6509, 29.691)
  line L18 (8.6509, 29.691) -> (12.9764, 29.691)
  line L19 (12.9764, 29.691) -> (17.3019, 29.691)
  line L20 (17.3019, 29.691) -> (21.6273, 29.691)
  line L21 (21.6273, 29.691) -> (21.6273, 31.691)
loft "Loft39" add profiles "cheekR_pa02", "cheekR_pb02" section 1 section 2 separate body makes body 39
ref_plane "WorkPlane79" through (-14.1143, 0, 0) normal (1, 0, 0) x (0, 1, 0)
sketch "cheekR_pa03" plane through (-14.1143, 0, 0) normal (1, 0, 0) x (0, 0, -1)
  line L0 (21.6273, 31.691) -> (17.3019, 31.691)
  line L1 (17.3019, 31.691) -> (12.9764, 31.691)
  line L2 (12.9764, 31.691) -> (8.6509, 31.691)
  line L3 (8.6509, 31.691) -> (4.3255, 31.691)
  line L4 (4.3255, 31.691) -> (0, 31.691)
  line L5 (0, 31.691) -> (-4.3255, 31.691)
  line L6 (-4.3255, 31.691) -> (-8.6509, 31.691)
  line L7 (-8.6509, 31.691) -> (-12.9764, 31.691)
  line L8 (-12.9764, 31.691) -> (-17.3019, 31.691)
  line L9 (-17.3019, 31.691) -> (-21.6273, 31.691)
  line L10 (-21.6273, 31.691) -> (-21.6273, 29.691)
  line L11 (-21.6273, 29.691) -> (-17.3019, 29.691)
  line L12 (-17.3019, 29.691) -> (-12.9764, 29.691)
  line L13 (-12.9764, 29.691) -> (-8.6509, 29.691)
  line L14 (-8.6509, 29.691) -> (-4.3255, 29.691)
  line L15 (-4.3255, 29.691) -> (0, 29.691)
  line L16 (0, 29.691) -> (4.3255, 29.691)
  line L17 (4.3255, 29.691) -> (8.6509, 29.691)
  line L18 (8.6509, 29.691) -> (12.9764, 29.691)
  line L19 (12.9764, 29.691) -> (17.3019, 29.691)
  line L20 (17.3019, 29.691) -> (21.6273, 29.691)
  line L21 (21.6273, 29.691) -> (21.6273, 31.691)
ref_plane "WorkPlane80" through (-9.8857, 0, 0) normal (1, 0, 0) x (0, 1, 0)
sketch "cheekR_pb03" plane through (-9.8857, 0, 0) normal (1, 0, 0) x (0, 0, -1)
  line L0 (20.994, 30.7409) -> (16.7952, 30.7409)
  line L1 (16.7952, 30.7409) -> (12.5964, 30.7409)
  line L2 (12.5964, 30.7409) -> (8.3976, 30.7409)
  line L3 (8.3976, 30.7409) -> (4.1988, 30.7409)
  line L4 (4.1988, 30.7409) -> (0, 30.7409)
  line L5 (0, 30.7409) -> (-4.1988, 30.7409)
  line L6 (-4.1988, 30.7409) -> (-8.3976, 30.7409)
  line L7 (-8.3976, 30.7409) -> (-12.5964, 30.7409)
  line L8 (-12.5964, 30.7409) -> (-16.7952, 30.7409)
  line L9 (-16.7952, 30.7409) -> (-20.994, 30.7409)
  line L10 (-20.994, 30.7409) -> (-20.994, 28.7409)
  line L11 (-20.994, 28.7409) -> (-16.7952, 28.7409)
  line L12 (-16.7952, 28.7409) -> (-12.5964, 28.7409)
  line L13 (-12.5964, 28.7409) -> (-8.3976, 28.7409)
  line L14 (-8.3976, 28.7409) -> (-4.1988, 28.7409)
  line L15 (-4.1988, 28.7409) -> (0, 28.7409)
  line L16 (0, 28.7409) -> (4.1988, 28.7409)
  line L17 (4.1988, 28.7409) -> (8.3976, 28.7409)
  line L18 (8.3976, 28.7409) -> (12.5964, 28.7409)
  line L19 (12.5964, 28.7409) -> (16.7952, 28.7409)
  line L20 (16.7952, 28.7409) -> (20.994, 28.7409)
  line L21 (20.994, 28.7409) -> (20.994, 30.7409)
loft "Loft40" add profiles "cheekR_pa03", "cheekR_pb03" section 1 section 2 separate body makes body 40
ref_plane "WorkPlane81" through (-10.6857, 0, 0) normal (1, 0, 0) x (0, 1, 0)
sketch "cheekR_pa04" plane through (-10.6857, 0, 0) normal (1, 0, 0) x (0, 0, -1)
  line L0 (20.994, 30.7409) -> (16.7952, 30.7409)
  line L1 (16.7952, 30.7409) -> (12.5964, 30.7409)
  line L2 (12.5964, 30.7409) -> (8.3976, 30.7409)
  line L3 (8.3976, 30.7409) -> (4.1988, 30.7409)
  line L4 (4.1988, 30.7409) -> (0, 30.7409)
  line L5 (0, 30.7409) -> (-4.1988, 30.7409)
  line L6 (-4.1988, 30.7409) -> (-8.3976, 30.7409)
  line L7 (-8.3976, 30.7409) -> (-12.5964, 30.7409)
  line L8 (-12.5964, 30.7409) -> (-16.7952, 30.7409)
  line L9 (-16.7952, 30.7409) -> (-20.994, 30.7409)
  line L10 (-20.994, 30.7409) -> (-20.994, 28.7409)
  line L11 (-20.994, 28.7409) -> (-16.7952, 28.7409)
  line L12 (-16.7952, 28.7409) -> (-12.5964, 28.7409)
  line L13 (-12.5964, 28.7409) -> (-8.3976, 28.7409)
  line L14 (-8.3976, 28.7409) -> (-4.1988, 28.7409)
  line L15 (-4.1988, 28.7409) -> (0, 28.7409)
  line L16 (0, 28.7409) -> (4.1988, 28.7409)
  line L17 (4.1988, 28.7409) -> (8.3976, 28.7409)
  line L18 (8.3976, 28.7409) -> (12.5964, 28.7409)
  line L19 (12.5964, 28.7409) -> (16.7952, 28.7409)
  line L20 (16.7952, 28.7409) -> (20.994, 28.7409)
  line L21 (20.994, 28.7409) -> (20.994, 30.7409)
ref_plane "WorkPlane82" through (-6.4571, 0, 0) normal (1, 0, 0) x (0, 1, 0)
sketch "cheekR_pb04" plane through (-6.4571, 0, 0) normal (1, 0, 0) x (0, 0, -1)
  line L0 (20.2355, 29.6033) -> (16.1884, 29.6033)
  line L1 (16.1884, 29.6033) -> (12.1413, 29.6033)
  line L2 (12.1413, 29.6033) -> (8.0942, 29.6033)
  line L3 (8.0942, 29.6033) -> (4.0471, 29.6033)
  line L4 (4.0471, 29.6033) -> (0, 29.6033)
  line L5 (0, 29.6033) -> (-4.0471, 29.6033)
  line L6 (-4.0471, 29.6033) -> (-8.0942, 29.6033)
  line L7 (-8.0942, 29.6033) -> (-12.1413, 29.6033)
  line L8 (-12.1413, 29.6033) -> (-16.1884, 29.6033)
  line L9 (-16.1884, 29.6033) -> (-20.2355, 29.6033)
  line L10 (-20.2355, 29.6033) -> (-20.2355, 27.6033)
  line L11 (-20.2355, 27.6033) -> (-16.1884, 27.6033)
  line L12 (-16.1884, 27.6033) -> (-12.1413, 27.6033)
  line L13 (-12.1413, 27.6033) -> (-8.0942, 27.6033)
  line L14 (-8.0942, 27.6033) -> (-4.0471, 27.6033)
  line L15 (-4.0471, 27.6033) -> (0, 27.6033)
  line L16 (0, 27.6033) -> (4.0471, 27.6033)
  line L17 (4.0471, 27.6033) -> (8.0942, 27.6033)
  line L18 (8.0942, 27.6033) -> (12.1413, 27.6033)
  line L19 (12.1413, 27.6033) -> (16.1884, 27.6033)
  line L20 (16.1884, 27.6033) -> (20.2355, 27.6033)
  line L21 (20.2355, 27.6033) -> (20.2355, 29.6033)
loft "Loft41" add profiles "cheekR_pa04", "cheekR_pb04" section 1 section 2 separate body makes body 41
ref_plane "WorkPlane83" through (-7.2571, 0, 0) normal (1, 0, 0) x (0, 1, 0)
sketch "cheekR_pa05" plane through (-7.2571, 0, 0) normal (1, 0, 0) x (0, 0, -1)
  line L0 (20.2355, 29.6033) -> (16.1884, 29.6033)
  line L1 (16.1884, 29.6033) -> (12.1413, 29.6033)
  line L2 (12.1413, 29.6033) -> (8.0942, 29.6033)
  line L3 (8.0942, 29.6033) -> (4.0471, 29.6033)
  line L4 (4.0471, 29.6033) -> (0, 29.6033)
  line L5 (0, 29.6033) -> (-4.0471, 29.6033)
  line L6 (-4.0471, 29.6033) -> (-8.0942, 29.6033)
  line L7 (-8.0942, 29.6033) -> (-12.1413, 29.6033)
  line L8 (-12.1413, 29.6033) -> (-16.1884, 29.6033)
  line L9 (-16.1884, 29.6033) -> (-20.2355, 29.6033)
  line L10 (-20.2355, 29.6033) -> (-20.2355, 27.6033)
  line L11 (-20.2355, 27.6033) -> (-16.1884, 27.6033)
  line L12 (-16.1884, 27.6033) -> (-12.1413, 27.6033)
  line L13 (-12.1413, 27.6033) -> (-8.0942, 27.6033)
  line L14 (-8.0942, 27.6033) -> (-4.0471, 27.6033)
  line L15 (-4.0471, 27.6033) -> (0, 27.6033)
  line L16 (0, 27.6033) -> (4.0471, 27.6033)
  line L17 (4.0471, 27.6033) -> (8.0942, 27.6033)
  line L18 (8.0942, 27.6033) -> (12.1413, 27.6033)
  line L19 (12.1413, 27.6033) -> (16.1884, 27.6033)
  line L20 (16.1884, 27.6033) -> (20.2355, 27.6033)
  line L21 (20.2355, 27.6033) -> (20.2355, 29.6033)
ref_plane "WorkPlane84" through (-3.0286, 0, 0) normal (1, 0, 0) x (0, 1, 0)
sketch "cheekR_pb05" plane through (-3.0286, 0, 0) normal (1, 0, 0) x (0, 0, -1)
  line L0 (19.3901, 28.3351) -> (15.5121, 28.3351)
  line L1 (15.5121, 28.3351) -> (11.6341, 28.3351)
  line L2 (11.6341, 28.3351) -> (7.756, 28.3351)
  line L3 (7.756, 28.3351) -> (3.878, 28.3351)
  line L4 (3.878, 28.3351) -> (0, 28.3351)
  line L5 (0, 28.3351) -> (-3.878, 28.3351)
  line L6 (-3.878, 28.3351) -> (-7.756, 28.3351)
  line L7 (-7.756, 28.3351) -> (-11.6341, 28.3351)
  line L8 (-11.6341, 28.3351) -> (-15.5121, 28.3351)
  line L9 (-15.5121, 28.3351) -> (-19.3901, 28.3351)
  line L10 (-19.3901, 28.3351) -> (-19.3901, 26.3351)
  line L11 (-19.3901, 26.3351) -> (-15.5121, 26.3351)
  line L12 (-15.5121, 26.3351) -> (-11.6341, 26.3351)
  line L13 (-11.6341, 26.3351) -> (-7.756, 26.3351)
  line L14 (-7.756, 26.3351) -> (-3.878, 26.3351)
  line L15 (-3.878, 26.3351) -> (0, 26.3351)
  line L16 (0, 26.3351) -> (3.878, 26.3351)
  line L17 (3.878, 26.3351) -> (7.756, 26.3351)
  line L18 (7.756, 26.3351) -> (11.6341, 26.3351)
  line L19 (11.6341, 26.3351) -> (15.5121, 26.3351)
  line L20 (15.5121, 26.3351) -> (19.3901, 26.3351)
  line L21 (19.3901, 26.3351) -> (19.3901, 28.3351)
loft "Loft42" add profiles "cheekR_pa05", "cheekR_pb05" section 1 section 2 separate body makes body 42
ref_plane "WorkPlane85" through (-3.8286, 0, 0) normal (1, 0, 0) x (0, 1, 0)
sketch "cheekR_pa06" plane through (-3.8286, 0, 0) normal (1, 0, 0) x (0, 0, -1)
  line L0 (19.3901, 28.3351) -> (15.5121, 28.3351)
  line L1 (15.5121, 28.3351) -> (11.6341, 28.3351)
  line L2 (11.6341, 28.3351) -> (7.756, 28.3351)
  line L3 (7.756, 28.3351) -> (3.878, 28.3351)
  line L4 (3.878, 28.3351) -> (0, 28.3351)
  line L5 (0, 28.3351) -> (-3.878, 28.3351)
  line L6 (-3.878, 28.3351) -> (-7.756, 28.3351)
  line L7 (-7.756, 28.3351) -> (-11.6341, 28.3351)
  line L8 (-11.6341, 28.3351) -> (-15.5121, 28.3351)
  line L9 (-15.5121, 28.3351) -> (-19.3901, 28.3351)
  line L10 (-19.3901, 28.3351) -> (-19.3901, 26.3351)
  line L11 (-19.3901, 26.3351) -> (-15.5121, 26.3351)
  line L12 (-15.5121, 26.3351) -> (-11.6341, 26.3351)
  line L13 (-11.6341, 26.3351) -> (-7.756, 26.3351)
  line L14 (-7.756, 26.3351) -> (-3.878, 26.3351)
  line L15 (-3.878, 26.3351) -> (0, 26.3351)
  line L16 (0, 26.3351) -> (3.878, 26.3351)
  line L17 (3.878, 26.3351) -> (7.756, 26.3351)
  line L18 (7.756, 26.3351) -> (11.6341, 26.3351)
  line L19 (11.6341, 26.3351) -> (15.5121, 26.3351)
  line L20 (15.5121, 26.3351) -> (19.3901, 26.3351)
  line L21 (19.3901, 26.3351) -> (19.3901, 28.3351)
ref_plane "WorkPlane86" through (0.4, 0, 0) normal (1, 0, 0) x (0, 1, 0)
sketch "cheekR_pb06" plane through (0.4, 0, 0) normal (1, 0, 0) x (0, 0, -1)
  line L0 (18.5, 27) -> (14.8, 27)
  line L1 (14.8, 27) -> (11.1, 27)
  line L2 (11.1, 27) -> (7.4, 27)
  line L3 (7.4, 27) -> (3.7, 27)
  line L4 (3.7, 27) -> (0, 27)
  line L5 (0, 27) -> (-3.7, 27)
  line L6 (-3.7, 27) -> (-7.4, 27)
  line L7 (-7.4, 27) -> (-11.1, 27)
  line L8 (-11.1, 27) -> (-14.8, 27)
  line L9 (-14.8, 27) -> (-18.5, 27)
  line L10 (-18.5, 27) -> (-18.5, 25)
  line L11 (-18.5, 25) -> (-14.8, 25)
  line L12 (-14.8, 25) -> (-11.1, 25)
  line L13 (-11.1, 25) -> (-7.4, 25)
  line L14 (-7.4, 25) -> (-3.7, 25)
  line L15 (-3.7, 25) -> (0, 25)
  line L16 (0, 25) -> (3.7, 25)
  line L17 (3.7, 25) -> (7.4, 25)
  line L18 (7.4, 25) -> (11.1, 25)
  line L19 (11.1, 25) -> (14.8, 25)
  line L20 (14.8, 25) -> (18.5, 25)
  line L21 (18.5, 25) -> (18.5, 27)
loft "Loft43" add profiles "cheekR_pa06", "cheekR_pb06" section 1 section 2 separate body makes body 43
ref_plane "WorkPlane87" through (-0.4, 0, 0) normal (1, 0, 0) x (0, 1, 0)
sketch "cheekR_pa07" plane through (-0.4, 0, 0) normal (1, 0, 0) x (0, 0, -1)
  line L0 (18.5, 27) -> (14.8, 27)
  line L1 (14.8, 27) -> (11.1, 27)
  line L2 (11.1, 27) -> (7.4, 27)
  line L3 (7.4, 27) -> (3.7, 27)
  line L4 (3.7, 27) -> (0, 27)
  line L5 (0, 27) -> (-3.7, 27)
  line L6 (-3.7, 27) -> (-7.4, 27)
  line L7 (-7.4, 27) -> (-11.1, 27)
  line L8 (-11.1, 27) -> (-14.8, 27)
  line L9 (-14.8, 27) -> (-18.5, 27)
  line L10 (-18.5, 27) -> (-18.5, 25)
  line L11 (-18.5, 25) -> (-14.8, 25)
  line L12 (-14.8, 25) -> (-11.1, 25)
  line L13 (-11.1, 25) -> (-7.4, 25)
  line L14 (-7.4, 25) -> (-3.7, 25)
  line L15 (-3.7, 25) -> (0, 25)
  line L16 (0, 25) -> (3.7, 25)
  line L17 (3.7, 25) -> (7.4, 25)
  line L18 (7.4, 25) -> (11.1, 25)
  line L19 (11.1, 25) -> (14.8, 25)
  line L20 (14.8, 25) -> (18.5, 25)
  line L21 (18.5, 25) -> (18.5, 27)
ref_plane "WorkPlane88" through (30.4, 0, 0) normal (1, 0, 0) x (0, 1, 0)
sketch "cheekR_pb07" plane through (30.4, 0, 0) normal (1, 0, 0) x (0, 0, -1)
  line L0 (18.5, 27) -> (14.8, 27)
  line L1 (14.8, 27) -> (11.1, 27)
  line L2 (11.1, 27) -> (7.4, 27)
  line L3 (7.4, 27) -> (3.7, 27)
  line L4 (3.7, 27) -> (0, 27)
  line L5 (0, 27) -> (-3.7, 27)
  line L6 (-3.7, 27) -> (-7.4, 27)
  line L7 (-7.4, 27) -> (-11.1, 27)
  line L8 (-11.1, 27) -> (-14.8, 27)
  line L9 (-14.8, 27) -> (-18.5, 27)
  line L10 (-18.5, 27) -> (-18.5, 25)
  line L11 (-18.5, 25) -> (-14.8, 25)
  line L12 (-14.8, 25) -> (-11.1, 25)
  line L13 (-11.1, 25) -> (-7.4, 25)
  line L14 (-7.4, 25) -> (-3.7, 25)
  line L15 (-3.7, 25) -> (0, 25)
  line L16 (0, 25) -> (3.7, 25)
  line L17 (3.7, 25) -> (7.4, 25)
  line L18 (7.4, 25) -> (11.1, 25)
  line L19 (11.1, 25) -> (14.8, 25)
  line L20 (14.8, 25) -> (18.5, 25)
  line L21 (18.5, 25) -> (18.5, 27)
loft "Loft44" add profiles "cheekR_pa07", "cheekR_pb07" section 1 section 2 separate body makes body 44
ref_plane "WorkPlane89" through (29.6, 0, 0) normal (1, 0, 0) x (0, 1, 0)
sketch "cheekR_pa08" plane through (29.6, 0, 0) normal (1, 0, 0) x (0, 0, -1)
  line L0 (18.5, 27) -> (14.8, 27)
  line L1 (14.8, 27) -> (11.1, 27)
  line L2 (11.1, 27) -> (7.4, 27)
  line L3 (7.4, 27) -> (3.7, 27)
  line L4 (3.7, 27) -> (0, 27)
  line L5 (0, 27) -> (-3.7, 27)
  line L6 (-3.7, 27) -> (-7.4, 27)
  line L7 (-7.4, 27) -> (-11.1, 27)
  line L8 (-11.1, 27) -> (-14.8, 27)
  line L9 (-14.8, 27) -> (-18.5, 27)
  line L10 (-18.5, 27) -> (-18.5, 25)
  line L11 (-18.5, 25) -> (-14.8, 25)
  line L12 (-14.8, 25) -> (-11.1, 25)
  line L13 (-11.1, 25) -> (-7.4, 25)
  line L14 (-7.4, 25) -> (-3.7, 25)
  line L15 (-3.7, 25) -> (0, 25)
  line L16 (0, 25) -> (3.7, 25)
  line L17 (3.7, 25) -> (7.4, 25)
  line L18 (7.4, 25) -> (11.1, 25)
  line L19 (11.1, 25) -> (14.8, 25)
  line L20 (14.8, 25) -> (18.5, 25)
  line L21 (18.5, 25) -> (18.5, 27)
ref_plane "WorkPlane90" through (60.4, 0, 0) normal (1, 0, 0) x (0, 1, 0)
sketch "cheekR_pb08" plane through (60.4, 0, 0) normal (1, 0, 0) x (0, 0, -1)
  line L0 (18.5, 27) -> (14.8, 27)
  line L1 (14.8, 27) -> (11.1, 27)
  line L2 (11.1, 27) -> (7.4, 27)
  line L3 (7.4, 27) -> (3.7, 27)
  line L4 (3.7, 27) -> (0, 27)
  line L5 (0, 27) -> (-3.7, 27)
  line L6 (-3.7, 27) -> (-7.4, 27)
  line L7 (-7.4, 27) -> (-11.1, 27)
  line L8 (-11.1, 27) -> (-14.8, 27)
  line L9 (-14.8, 27) -> (-18.5, 27)
  line L10 (-18.5, 27) -> (-18.5, 25)
  line L11 (-18.5, 25) -> (-14.8, 25)
  line L12 (-14.8, 25) -> (-11.1, 25)
  line L13 (-11.1, 25) -> (-7.4, 25)
  line L14 (-7.4, 25) -> (-3.7, 25)
  line L15 (-3.7, 25) -> (0, 25)
  line L16 (0, 25) -> (3.7, 25)
  line L17 (3.7, 25) -> (7.4, 25)
  line L18 (7.4, 25) -> (11.1, 25)
  line L19 (11.1, 25) -> (14.8, 25)
  line L20 (14.8, 25) -> (18.5, 25)
  line L21 (18.5, 25) -> (18.5, 27)
loft "Loft45" add profiles "cheekR_pa08", "cheekR_pb08" section 1 section 2 separate body makes body 45
ref_plane "WorkPlane91" through (59.6, 0, 0) normal (1, 0, 0) x (0, 1, 0)
sketch "cheekR_pa09" plane through (59.6, 0, 0) normal (1, 0, 0) x (0, 0, -1)
  line L0 (18.5, 27) -> (14.8, 27)
  line L1 (14.8, 27) -> (11.1, 27)
  line L2 (11.1, 27) -> (7.4, 27)
  line L3 (7.4, 27) -> (3.7, 27)
  line L4 (3.7, 27) -> (0, 27)
  line L5 (0, 27) -> (-3.7, 27)
  line L6 (-3.7, 27) -> (-7.4, 27)
  line L7 (-7.4, 27) -> (-11.1, 27)
  line L8 (-11.1, 27) -> (-14.8, 27)
  line L9 (-14.8, 27) -> (-18.5, 27)
  line L10 (-18.5, 27) -> (-18.5, 25)
  line L11 (-18.5, 25) -> (-14.8, 25)
  line L12 (-14.8, 25) -> (-11.1, 25)
  line L13 (-11.1, 25) -> (-7.4, 25)
  line L14 (-7.4, 25) -> (-3.7, 25)
  line L15 (-3.7, 25) -> (0, 25)
  line L16 (0, 25) -> (3.7, 25)
  line L17 (3.7, 25) -> (7.4, 25)
  line L18 (7.4, 25) -> (11.1, 25)
  line L19 (11.1, 25) -> (14.8, 25)
  line L20 (14.8, 25) -> (18.5, 25)
  line L21 (18.5, 25) -> (18.5, 27)
ref_plane "WorkPlane92" through (90.4, 0, 0) normal (1, 0, 0) x (0, 1, 0)
sketch "cheekR_pb09" plane through (90.4, 0, 0) normal (1, 0, 0) x (0, 0, -1)
  line L0 (18.5, 27) -> (14.8, 27)
  line L1 (14.8, 27) -> (11.1, 27)
  line L2 (11.1, 27) -> (7.4, 27)
  line L3 (7.4, 27) -> (3.7, 27)
  line L4 (3.7, 27) -> (0, 27)
  line L5 (0, 27) -> (-3.7, 27)
  line L6 (-3.7, 27) -> (-7.4, 27)
  line L7 (-7.4, 27) -> (-11.1, 27)
  line L8 (-11.1, 27) -> (-14.8, 27)
  line L9 (-14.8, 27) -> (-18.5, 27)
  line L10 (-18.5, 27) -> (-18.5, 25)
  line L11 (-18.5, 25) -> (-14.8, 25)
  line L12 (-14.8, 25) -> (-11.1, 25)
  line L13 (-11.1, 25) -> (-7.4, 25)
  line L14 (-7.4, 25) -> (-3.7, 25)
  line L15 (-3.7, 25) -> (0, 25)
  line L16 (0, 25) -> (3.7, 25)
  line L17 (3.7, 25) -> (7.4, 25)
  line L18 (7.4, 25) -> (11.1, 25)
  line L19 (11.1, 25) -> (14.8, 25)
  line L20 (14.8, 25) -> (18.5, 25)
  line L21 (18.5, 25) -> (18.5, 27)
loft "Loft46" add profiles "cheekR_pa09", "cheekR_pb09" section 1 section 2 separate body makes body 46
ref_plane "WorkPlane93" through (89.6, 0, 0) normal (1, 0, 0) x (0, 1, 0)